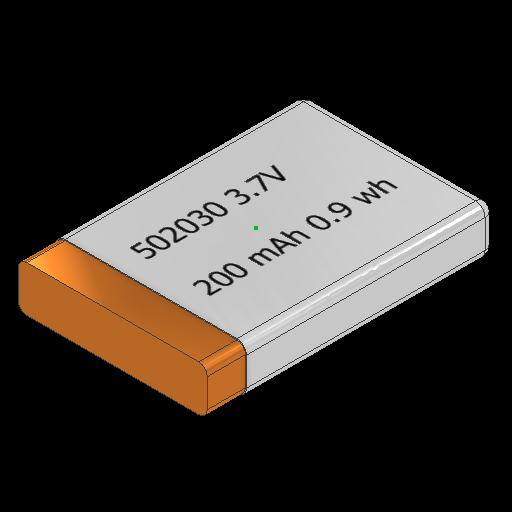
# Autodesk Inventor part: Li-Ion_akku_502030
Saved by Autodesk Inventor 2027.1 (Build 311270010, 270A)
## iProperties
Created: 2026-10-10
Part Number: Li-Ion_akku_502030
Material: Generisch
Document SubType Name: Modeling
Designer: josia
Density: 1 g/cm^3
Appearance: Vorgabe
Author: josia
Autodesk Inventor part; units mm, degrees
ref_plane "YZ Plane" through (0, 0, 0) normal (1, 0, 0) x (0, 1, 0)
ref_plane "XZ Plane" through (0, 0, 0) normal (0, 1, 0) x (-1, 0, 0)
ref_plane "XY Plane" through (0, 0, 0) normal (0, 0, 1) x (1, 0, 0)
sketch "Skizze1" plane through (0, 0, 0) normal (0, 1, 0) x (-1, 0, 0)
  line L0 (-10, -15) -> (10, -15)
  line L1 (10, -15) -> (10, 15)
  line L2 (10, 15) -> (-10, 15)
  line L3 (-10, 15) -> (-10, -15)
  line L4 (-10, -15) -> (10, 15) construction
  line L5 (10, -15) -> (-10, 15) construction
  point P0 (0, 0)
  dimension "d0" = 20
  dimension "d1" = 30
  constraints: 12 end point, 2 midpoint, 2 parallel, 1 horizontal, 1 perpendicular
  measures "d0" distance of L2.end L1.end
  measures "d1" distance of L1.end L0.end
extrude "Extrusion1" add sketch "Skizze1" along normal blind 5
sketch "Skizze2" plane through (0, 5, 0) normal (0, 1, 0) x (1, 0, 0)
  line L0 (-10, -15) -> (10, -15) projected
  line L1 (10, -15) -> (10, 15) projected
  line L2 (-10, -15) -> (10, -15)
  line L3 (10, -15) -> (10, -11)
  line L4 (10, -11) -> (-10, -11)
  line L5 (-10, -11) -> (-10, -15)
  point P0 (0, 0)
  dimension "d4" = 4
  constraints: 8 end point, 2 parallel, 1 horizontal, 1 perpendicular, 1 point on line
  measures "d4" distance of L3.end L2.end
extrude "Extrusion2" cut sketch "Skizze2" against normal blind 0.1
sketch "Skizze3" plane through (10, 0, 15) normal (1, 0, 0) x (0, 0, -1)
  line L0 (0, 4.9) -> (4, 4.9) projected
  line L1 (30, 0) -> (0, 0) projected
  line L2 (0, 4.9) -> (4, 4.9)
  line L3 (4, 4.9) -> (4, 0)
  line L4 (4, 0) -> (0, 0)
  line L5 (0, 0) -> (0, 4.9)
  point P0 (15, 0)
  dimension "d7" = 4
  constraints: 8 end point, 2 parallel, 1 horizontal, 1 perpendicular, 1 point on line
  measures "d7" distance of L3.end L4.end
extrude "Extrusion3" cut sketch "Skizze3" against normal blind 0.1
sketch "Skizze4" plane through (0, 0, 0) normal (0, -1, 0) x (1, 0, 0)
  line L0 (-10, 15) -> (9.9, 15) projected
  line L1 (-10, 11) -> (10, 11) projected
  line L2 (9.9, 15) -> (-10, 15)
  line L3 (-10, 15) -> (-10, 11)
  line L4 (-10, 11) -> (9.9, 11)
  line L5 (9.9, 11) -> (9.9, 15)
  point P0 (0, 0)
  constraints: 8 end point, 2 parallel, 1 horizontal, 1 perpendicular
extrude "Extrusion4" cut sketch "Skizze4" against normal blind 0.1
sketch "Skizze5" plane through (-10, 0, -15) normal (-1, 0, 0) x (0, 0, 1)
  line L0 (30, 4.9) -> (26, 4.9) projected
  line L1 (30, 0.1) -> (30, 4.9) projected
  line L2 (26, 4.9) -> (30, 4.9)
  line L3 (30, 4.9) -> (30, 0.1)
  line L4 (30, 0.1) -> (26, 0.1)
  line L5 (26, 0.1) -> (26, 4.9)
  point P0 (15, 0)
  constraints: 8 end point, 2 parallel, 1 horizontal, 1 perpendicular
extrude "Extrusion5" cut sketch "Skizze5" against normal blind 0.1
fillet "Rundung1" radius 1 8 edges at (-10, 5, -2) (10, 5, -2) (10, 0, -2) (-10, 0, -2) (0, 5, -15) (10, 2.5, -15) (0, 0, -15) (-10, 2.5, -15)
sketch "Skizze6" plane through (0, 0, 0) normal (0, -1, 0) x (1, 0, 0)
  line L0 (4.9272, 7.579) -> (4.9272, -15.7134) construction
  line L1 (4.9272, -15.7134) -> (-9.1557, -15.7134) construction
  line L2 (-9.1557, -15.7134) -> (-9.1557, 7.579) construction
  line L3 (-9.1557, 7.579) -> (4.9272, 7.579) construction
  point P0 (0, 0)
  constraints: 2 other
sketch "Skizze7" plane through (0, 5, 0) normal (0, 1, 0) x (1, 0, 0)
  line L0 (8.9586, 14.6384) -> (8.9586, -8.654) construction
  line L1 (8.9586, -8.654) -> (-5.1243, -8.654) construction
  line L2 (-5.1243, -8.654) -> (-5.1243, 14.6384) construction
  line L3 (-5.1243, 14.6384) -> (8.9586, 14.6384) construction
  line L4 (8.3494, 15.0325) -> (8.3494, -8.2598) construction
  line L5 (8.3494, -8.2598) -> (-5.7335, -8.2598) construction
  line L6 (-5.7335, -8.2598) -> (-5.7335, 15.0325) construction
  line L7 (-5.7335, 15.0325) -> (8.3494, 15.0325) construction
  line L8 (-4.896, -8.65) -> (-4.896, 14.6424) construction
  line L9 (-4.896, 14.6424) -> (9.187, 14.6424) construction
  line L10 (9.187, 14.6424) -> (9.187, -8.65) construction
  line L11 (9.187, -8.65) -> (-4.896, -8.65) construction
  point P0 (0, 0)
  constraints: 4 other
sketch "Skizze8" plane through (-9.4359, 0.1, 15) normal (0, 0, 1) x (1, 0, 0)
  arc A0 (-0.4641, 0.4641) -> (0, 0) centre (0.4359, 0.9) ccw projected
  line L0 (0, 0) -> (18.8718, 0) projected
  arc A1 (18.8718, 0) -> (19.3359, 0.4641) centre (18.4359, 0.9) ccw projected
  line L1 (19.3359, 0.4641) -> (19.3359, 4.3359) projected
  arc A2 (19.3359, 4.3359) -> (18.8718, 4.8) centre (18.4359, 3.9) ccw projected
  line L2 (18.8718, 4.8) -> (0, 4.8) projected
  arc A3 (0, 4.8) -> (-0.4641, 4.3359) centre (0.4359, 3.9) ccw projected
  line L3 (-0.4641, 4.3359) -> (-0.4641, 0.4641) projected
  line L4 (18.4359, 3.9) -> (0.4359, 3.9) projected
  circle A4 centre (0.4359, 3.9) radius 0.9
  line L5 (0.4359, 0.9) -> (18.4359, 0.9) projected
  circle A5 centre (0.4359, 0.9) radius 0.9
  circle A6 centre (18.4359, 3.9) radius 0.9
  line L6 (19.4359, 0.9) -> (18.4359, 0.9) projected
  circle A7 centre (18.4359, 0.9) radius 0.9
  point P0 (9.4359, -0.1)
  point P1 (-0.4641, 3.9)
  point P2 (0.4359, 4.8)
  point P3 (0.4359, 0)
  point P4 (-0.4641, 0.9)
  point P5 (19.3359, 0.9)
  point P6 (18.4359, 0)
  point P7 (18.4359, 4.8)
  point P8 (19.3359, 3.9)
  constraints: 4 centre point, 4 coincident
extrude "Extrusion6" cut sketch "Skizze8" against normal blind 4 contours L3 A5 L0 A0 | L3 A3 L2 A4 | A7 L1 A1 L0 | L2 A2 L1 A6
